Autodesk Fusion 360 part; units mm, degrees
(part 2 of 2)
equation "spigot_d = 8.5 mm" comment "ASSUMPTION: register FR-05: hole for the 8 mm locating spigot H-05"
equation "spigot_slot = 14 mm" comment "ASSUMPTION: register FR-05: slot length for the second spigot"
equation "spigot_edge = spigot_inset" comment "CALCULATION: the skeleton's spigot_inset: spigots 100 from each end of the edge (PM ruling 2026-10-31, R-J13)"
equation "bolt_edge = bolt_edge_inset" comment "CALCULATION: the skeleton's bolt_edge_inset: end bolts 220 in from the panel's ends, evenly spaced, every bolt 30 or more from any stile (PM ruling 2026-10-31, R-J14)"
equation "n_side_jnt = 3" comment "SOURCE: register J-WALL-02, J-FRONT-01: 3 bolts up each side panel"
equation "side_jnt_pitch = ( pnl_h - 2 * bolt_edge ) / ( n_side_jnt - 1 )" comment "CALCULATION: equal pitch of the 3 bolts up the corner and decor joints"
equation "pocket_w = 60 mm" comment "ASSUMPTION: register FR-10: fill left out 60 x 60 next to each bolt for the key"
equation "corner_z0 = panel_z0 + back_ph + seam_gap" comment "CALCULATION: bottom of the back panel row this side panel meets at the corner (B1/B2 or B3/B4, skeleton P04)"
equation "corner_bolt_pitch = ( back_ph - 2 * bolt_edge ) / ( n_side_jnt - 1 )" comment "CALCULATION: J-WALL-02 bolts run along the back panel's edge: 220, 559.31, 898.61 on its 1118.61 (joints register 2.9)"
equation "n_len_bolt = n_base_bolt" comment "CALCULATION: the skeleton's n_base_bolt (4): the same count on J-WALL-01 and the J-CEIL-01 side edges (register 2.9)"
equation "ceil_bolt_pitch = ( wall_depth - 2 * bolt_edge ) / ( n_len_bolt - 1 )" comment "CALCULATION: J-CEIL-01 side edge: 4 bolts along the ceiling's 1495 from Y -645 (its front edge), 220 rule, pitch 351.67 on P04; CEILING drills the same (PM ruling 2026-10-31 16:55; joints register 2.9)"
equation "len_bolt_pitch = ( pnl_len - 2 * bolt_edge ) / ( n_len_bolt - 1 )" comment "CALCULATION: even pitch of the bolts along the panel"
equation "felt_t = 9 mm" comment "SOURCE: plan VT03-PET 9 mm PET felt; HW-SEL A3; D-31 (the factory's felt)"
equation "tray_t = 0.5 mm" comment "CONFIRMED: D-37: galvanised steel tray 0.5 mm"
equation "tray_h = cass_t" comment "CONFIRMED: PM ruling 2026-10-31 (WALL group, option 1): the wall cassettes use the ceiling's tray, returns the full cassette depth (34) turned in as lips that hold the felt, no ribs; settles H09 for the walls"
equation "lip_w = 12 mm" comment "CONFIRMED: PM ruling 2026-10-31 (WALL group, option 1): 12 mm lips hold the felt edge"
equation "bend_r = tray_t" comment "ASSUMPTION: inside bend radius 1 x t for 0.5 mm DX51D (the sheet metal rule's bend radius is its Thickness); the factory's tooling sets it (guideline 9)"
equation "felt_c = 1 mm" comment "ASSUMPTION: felt edge clearance inside the returns, as the ceiling cassette"
equation "gap_h = tray_h - felt_t - 2 * tray_t" comment "CALCULATION: air gap between the tray base and the felt (24): the acoustic gap (D-17) and the cable path (D-26)"
equation "cass_len = wall_depth - stack_t + cass_t" comment "CALCULATION: = 1448: from the decor back plate to past the back cassette's face, closing the inside corner (D-57)"
equation "cass_h = pod_h - outer_t - lin_gap - ( panel_z0 + side_h + seam_gap )" comment "CALCULATION: lower: the panel height; upper: stops lin_gap under the roof frame so it floats (D-57)"
equation "clip_zone_h = 60 mm" comment "ASSUMPTION: height of each reserved clip zone (H03: no clip named)"
equation "clip_zone_dz = 100 mm" comment "ASSUMPTION: clip zone centre from the cassette's top and bottom edges (H03)"
equation "stopw_od = 20 mm" comment "SOURCE: joints register H-08: stop washer Ø10.5 x Ø20 x 1.5 (PROPOSED part)"
equation "stopw_id = 10.5 mm" comment "SOURCE: joints register H-08"
equation "stopw_t = 1.5 mm" comment "SOURCE: joints register H-08: rivnut head 0.76 + washer 1.5 = the 2.26 stop (R-J5)"
equation "rivnut_head_d = 12.96 mm" comment "SOURCE: Sherex CAH3-610-4.2 head Ø12.96 (joints register H-03, SHX)"
equation "rivnut_head_t = 0.76 mm" comment "SOURCE: Sherex CAH3-610-4.2 head 0.76 ±0.08 (H-03, SHX)"
equation "rivnut_body_d = 9.5 mm" comment "SOURCE: Sherex CAH3-610-4.2 body Ø9.50 max (H-03, SHX)"
equation "rivnut_len = 10.16 mm" comment "SOURCE: Sherex CAH3-610-4.2 installed length 10.16 max under the head (H-03, SHX); the bulge inside the tube is not modelled"
equation "m6_d = 6 mm" comment "CALCULATION: M6 threads shown at their 6 mm major diameter (no modelled thread)"
equation "spigot_pin_d = 8 mm" comment "SOURCE: joints register H-05: Ø8 stainless pin (PROPOSED, assumption sizes)"
equation "spigot_proud = 8 mm" comment "SOURCE: joints register H-05: stands 8 proud (read as: of the joint face)"
equation "spigot_thread_l = 10 mm" comment "ASSUMPTION: M6 thread into the spigot rivnut; H-05 gives no length; 10 stays inside the rivnut's 10.16"
equation "d165 = panel_z0 + side_h + seam_gap"
equation "d167 = ( ( pod_w / 2 - skin_t - bond_t ) ) - ( ( pod_w / 2 - outer_t ) )"
equation "d168 = ( pod_d / 2 - skin_t ) - ( pod_d / 2 - wall_depth + seam_gap )"
equation "d169 = abs(( pod_w / 2 - outer_t ))"
equation "d170 = abs(pod_d / 2 - wall_depth + seam_gap)"
equation "d171 = ( ( panel_z0 + side_h + seam_gap ) + tube_w ) - ( panel_z0 + side_h + seam_gap )"
equation "d173 = ( panel_z0 + side_h + seam_gap ) + tube_t"
equation "d175 = ( ( ( pod_w / 2 - skin_t - bond_t ) ) - tube_t ) - ( ( ( pod_w / 2 - outer_t ) ) + tube_t )"
equation "d176 = ( pod_d / 2 - skin_t ) - ( pod_d / 2 - wall_depth + seam_gap )"
equation "d177 = abs(( ( pod_w / 2 - outer_t ) ) + tube_t)"
equation "d178 = abs(pod_d / 2 - wall_depth + seam_gap)"
equation "d179 = ( ( ( panel_z0 + side_h + seam_gap ) + tube_w ) - tube_t ) - ( ( panel_z0 + side_h + seam_gap ) + tube_t )"
equation "d181 = ( pod_h ) - top_h"
equation "d183 = ( ( pod_w / 2 - skin_t - bond_t ) ) - ( ( pod_w / 2 - outer_t ) )"
equation "d184 = ( pod_d / 2 - skin_t ) - ( pod_d / 2 - wall_depth + seam_gap )"
equation "d185 = abs(( pod_w / 2 - outer_t ))"
equation "d186 = abs(pod_d / 2 - wall_depth + seam_gap)"
equation "d187 = ( pod_h ) - ( ( pod_h ) - top_h )"
equation "d189 = ( ( pod_h ) - top_h ) + tube_t"
equation "d191 = ( ( ( pod_w / 2 - skin_t - bond_t ) ) - tube_t ) - ( ( ( pod_w / 2 - outer_t ) ) + tube_t )"
equation "d192 = ( pod_d / 2 - skin_t ) - ( pod_d / 2 - wall_depth + seam_gap )"
equation "d193 = abs(( ( pod_w / 2 - outer_t ) ) + tube_t)"
equation "d194 = abs(pod_d / 2 - wall_depth + seam_gap)"
equation "d195 = ( ( pod_h ) - tube_t ) - ( ( ( pod_h ) - top_h ) + tube_t )"
equation "d197 = ( panel_z0 + side_h + seam_gap ) + tube_w"
equation "d199 = ( ( pod_w / 2 - skin_t - bond_t ) ) - ( ( pod_w / 2 - outer_t ) )"
equation "d200 = ( ( pod_d / 2 - wall_depth + seam_gap ) + tube_w ) - ( pod_d / 2 - wall_depth + seam_gap )"
equation "d201 = abs(( pod_w / 2 - outer_t ))"
equation "d202 = abs(pod_d / 2 - wall_depth + seam_gap)"
equation "d203 = ( ( pod_h ) - top_h ) - ( ( panel_z0 + side_h + seam_gap ) + tube_w )"
equation "d205 = ( panel_z0 + side_h + seam_gap ) + tube_w"
equation "d207 = ( ( ( pod_w / 2 - skin_t - bond_t ) ) - tube_t ) - ( ( ( pod_w / 2 - outer_t ) ) + tube_t )"
equation "d208 = ( ( ( pod_d / 2 - wall_depth + seam_gap ) + tube_w ) - tube_t ) - ( ( pod_d / 2 - wall_depth + seam_gap ) + tube_t )"
equation "d209 = abs(( ( pod_w / 2 - outer_t ) ) + tube_t)"
equation "d210 = abs(( pod_d / 2 - wall_depth + seam_gap ) + tube_t)"
equation "d211 = ( ( pod_h ) - top_h ) - ( ( panel_z0 + side_h + seam_gap ) + tube_w )"
equation "d213 = ( panel_z0 + side_h + seam_gap ) + tube_w"
equation "d215 = ( ( pod_w / 2 - skin_t - bond_t ) ) - ( ( pod_w / 2 - outer_t ) )"
equation "d216 = ( pod_d / 2 - skin_t ) - ( ( pod_d / 2 - skin_t ) - corner_w )"
equation "d217 = abs(( pod_w / 2 - outer_t ))"
equation "d218 = abs(( pod_d / 2 - skin_t ) - corner_w)"
equation "d219 = ( ( pod_h ) - top_h ) - ( ( panel_z0 + side_h + seam_gap ) + tube_w )"
equation "d221 = ( panel_z0 + side_h + seam_gap ) + tube_w"
equation "d223 = ( ( ( pod_w / 2 - skin_t - bond_t ) ) - tube_t ) - ( ( ( pod_w / 2 - outer_t ) ) + tube_t )"
equation "d224 = ( ( pod_d / 2 - skin_t ) - tube_t ) - ( ( ( pod_d / 2 - skin_t ) - corner_w ) + tube_t )"
equation "d225 = abs(( ( pod_w / 2 - outer_t ) ) + tube_t)"
equation "d226 = abs(( ( pod_d / 2 - skin_t ) - corner_w ) + tube_t)"
equation "d227 = ( ( pod_h ) - top_h ) - ( ( panel_z0 + side_h + seam_gap ) + tube_w )"
equation "d229 = ( panel_z0 + side_h + seam_gap ) + tube_w"
equation "d231 = ( ( pod_w / 2 - skin_t - bond_t ) ) - ( ( pod_w / 2 - outer_t ) )"
equation "d232 = ( ( pod_d / 2 - wall_depth + seam_gap ) + stile_pitch + tube_w ) - ( ( pod_d / 2 - wall_depth + seam_gap ) + stile_pitch )"
equation "d233 = abs(( pod_w / 2 - outer_t ))"
equation "d234 = abs(( pod_d / 2 - wall_depth + seam_gap ) + stile_pitch)"
equation "d235 = ( ( pod_h ) - top_h ) - ( ( panel_z0 + side_h + seam_gap ) + tube_w )"
equation "d237 = ( panel_z0 + side_h + seam_gap ) + tube_w"
equation "d239 = ( ( ( pod_w / 2 - skin_t - bond_t ) ) - stud_t ) - ( ( ( pod_w / 2 - outer_t ) ) + stud_t )"
equation "d240 = ( ( ( pod_d / 2 - wall_depth + seam_gap ) + stile_pitch + tube_w ) - stud_t ) - ( ( ( pod_d / 2 - wall_depth + seam_gap ) + stile_pitch ) + stud_t )"
equation "d241 = abs(( ( pod_w / 2 - outer_t ) ) + stud_t)"
equation "d242 = abs(( ( pod_d / 2 - wall_depth + seam_gap ) + stile_pitch ) + stud_t)"
equation "d243 = ( ( pod_h ) - top_h ) - ( ( panel_z0 + side_h + seam_gap ) + tube_w )"
equation "d245 = stile_n_mid"
equation "d247 = stile_pitch"
equation "d249 = ( panel_z0 + side_h + seam_gap ) + skin_setback"
equation "d251 = ( ( pod_w / 2 ) ) - ( ( pod_w / 2 - skin_t ) )"
equation "d252 = ( pod_d / 2 ) - ( pod_d / 2 - wall_depth + seam_gap )"
equation "d253 = abs(( pod_w / 2 - skin_t ))"
equation "d254 = abs(pod_d / 2 - wall_depth + seam_gap)"
equation "d255 = ( pod_h ) - ( ( panel_z0 + side_h + seam_gap ) + skin_setback )"
equation "d257 = ( panel_z0 + side_h + seam_gap ) + skin_setback"
equation "d259 = ( ( pod_w / 2 - skin_t ) ) - ( ( pod_w / 2 - skin_t - skin_ret ) )"
equation "d260 = ( pod_d / 2 ) - ( pod_d / 2 - skin_t )"
equation "d261 = abs(( pod_w / 2 - skin_t - skin_ret ))"
equation "d262 = abs(pod_d / 2 - skin_t)"
equation "d263 = ( pod_h ) - ( ( panel_z0 + side_h + seam_gap ) + skin_setback )"
equation "d265 = ( panel_z0 + side_h + seam_gap ) + tube_w"
equation "d267 = ( ( pod_w / 2 - skin_t - bond_t ) ) - ( ( pod_w / 2 - outer_t ) )"
equation "d268 = ( ( pod_d / 2 - wall_depth + seam_gap ) + stile_pitch ) - ( ( pod_d / 2 - wall_depth + seam_gap ) + tube_w )"
equation "d269 = abs(( pod_w / 2 - outer_t ))"
equation "d270 = abs(( pod_d / 2 - wall_depth + seam_gap ) + tube_w)"
equation "d271 = ( ( pod_h ) - top_h ) - ( ( panel_z0 + side_h + seam_gap ) + tube_w )"
equation "d273 = stile_n_mid"
equation "d275 = stile_pitch"
equation "d277 = ( panel_z0 + side_h + seam_gap ) + tube_w"
equation "d279 = ( ( pod_w / 2 - skin_t - bond_t ) ) - ( ( pod_w / 2 - outer_t ) )"
equation "d280 = ( ( pod_d / 2 - skin_t ) - corner_w ) - ( ( pod_d / 2 - wall_depth + seam_gap ) + stile_n_mid * stile_pitch + tube_w )"
equation "d281 = abs(( pod_w / 2 - outer_t ))"
equation "d282 = abs(( pod_d / 2 - wall_depth + seam_gap ) + stile_n_mid * stile_pitch + tube_w)"
equation "d283 = ( ( pod_h ) - top_h ) - ( ( panel_z0 + side_h + seam_gap ) + tube_w )"
equation "d285 = ( panel_z0 + side_h + seam_gap ) + tube_w"
equation "d287 = ( ( pod_w / 2 - skin_t - bond_t ) ) - ( ( pod_w / 2 - outer_t ) )"
equation "d288 = ( ( ( pod_d / 2 - wall_depth + seam_gap ) + bolt_edge + 0 * len_bolt_pitch ) + pocket_w / 2 ) - ( ( ( pod_d / 2 - wall_depth + seam_gap ) + bolt_edge + 0 * len_bolt_pitch ) - pocket_w / 2 )"
equation "d289 = abs(( pod_w / 2 - outer_t ))"
equation "d290 = abs(( ( pod_d / 2 - wall_depth + seam_gap ) + bolt_edge + 0 * len_bolt_pitch ) - pocket_w / 2)"
equation "d291 = ( ( ( panel_z0 + side_h + seam_gap ) + tube_w ) + pocket_w ) - ( ( panel_z0 + side_h + seam_gap ) + tube_w )"
equation "d293 = ( panel_z0 + side_h + seam_gap ) + tube_w"
equation "d295 = ( ( pod_w / 2 - skin_t - bond_t ) ) - ( ( pod_w / 2 - outer_t ) )"
equation "d296 = ( ( ( pod_d / 2 - wall_depth + seam_gap ) + bolt_edge + 1 * len_bolt_pitch ) + pocket_w / 2 ) - ( ( ( pod_d / 2 - wall_depth + seam_gap ) + bolt_edge + 1 * len_bolt_pitch ) - pocket_w / 2 )"
equation "d297 = abs(( pod_w / 2 - outer_t ))"
equation "d298 = abs(( ( pod_d / 2 - wall_depth + seam_gap ) + bolt_edge + 1 * len_bolt_pitch ) - pocket_w / 2)"
equation "d299 = ( ( ( panel_z0 + side_h + seam_gap ) + tube_w ) + pocket_w ) - ( ( panel_z0 + side_h + seam_gap ) + tube_w )"
equation "d301 = ( panel_z0 + side_h + seam_gap ) + tube_w"
equation "d303 = ( ( pod_w / 2 - skin_t - bond_t ) ) - ( ( pod_w / 2 - outer_t ) )"
equation "d304 = ( ( ( pod_d / 2 - wall_depth + seam_gap ) + bolt_edge + 2 * len_bolt_pitch ) + pocket_w / 2 ) - ( ( ( pod_d / 2 - wall_depth + seam_gap ) + bolt_edge + 2 * len_bolt_pitch ) - pocket_w / 2 )"
equation "d305 = abs(( pod_w / 2 - outer_t ))"
equation "d306 = abs(( ( pod_d / 2 - wall_depth + seam_gap ) + bolt_edge + 2 * len_bolt_pitch ) - pocket_w / 2)"
equation "d307 = ( ( ( panel_z0 + side_h + seam_gap ) + tube_w ) + pocket_w ) - ( ( panel_z0 + side_h + seam_gap ) + tube_w )"
equation "d309 = ( panel_z0 + side_h + seam_gap ) + tube_w"
equation "d311 = ( ( pod_w / 2 - skin_t - bond_t ) ) - ( ( pod_w / 2 - outer_t ) )"
equation "d312 = ( ( ( pod_d / 2 - wall_depth + seam_gap ) + bolt_edge + 3 * len_bolt_pitch ) + pocket_w / 2 ) - ( ( ( pod_d / 2 - wall_depth + seam_gap ) + bolt_edge + 3 * len_bolt_pitch ) - pocket_w / 2 )"
equation "d313 = abs(( pod_w / 2 - outer_t ))"
equation "d314 = abs(( ( pod_d / 2 - wall_depth + seam_gap ) + bolt_edge + 3 * len_bolt_pitch ) - pocket_w / 2)"
equation "d315 = ( ( ( panel_z0 + side_h + seam_gap ) + tube_w ) + pocket_w ) - ( ( panel_z0 + side_h + seam_gap ) + tube_w )"
equation "d317 = ( ( ( panel_z0 + side_h + seam_gap ) + bolt_edge ) + 0 * side_jnt_pitch ) - pocket_w / 2"
equation "d319 = ( ( pod_w / 2 - skin_t - bond_t ) ) - ( ( pod_w / 2 - outer_t ) )"
equation "d320 = ( ( pod_d / 2 - wall_depth + seam_gap ) + tube_w + pocket_w ) - ( ( pod_d / 2 - wall_depth + seam_gap ) + tube_w )"
equation "d321 = abs(( pod_w / 2 - outer_t ))"
equation "d322 = abs(( pod_d / 2 - wall_depth + seam_gap ) + tube_w)"
equation "d323 = ( ( ( ( panel_z0 + side_h + seam_gap ) + bolt_edge ) + 0 * side_jnt_pitch ) + pocket_w / 2 ) - ( ( ( ( panel_z0 + side_h + seam_gap ) + bolt_edge ) + 0 * side_jnt_pitch ) - pocket_w / 2 )"
equation "d325 = ( ( ( panel_z0 + side_h + seam_gap ) + bolt_edge ) + 1 * side_jnt_pitch ) - pocket_w / 2"
equation "d327 = ( ( pod_w / 2 - skin_t - bond_t ) ) - ( ( pod_w / 2 - outer_t ) )"
equation "d328 = ( ( pod_d / 2 - wall_depth + seam_gap ) + tube_w + pocket_w ) - ( ( pod_d / 2 - wall_depth + seam_gap ) + tube_w )"
equation "d329 = abs(( pod_w / 2 - outer_t ))"
equation "d330 = abs(( pod_d / 2 - wall_depth + seam_gap ) + tube_w)"
equation "d331 = ( ( ( ( panel_z0 + side_h + seam_gap ) + bolt_edge ) + 1 * side_jnt_pitch ) + pocket_w / 2 ) - ( ( ( ( panel_z0 + side_h + seam_gap ) + bolt_edge ) + 1 * side_jnt_pitch ) - pocket_w / 2 )"
equation "d333 = ( ( ( panel_z0 + side_h + seam_gap ) + bolt_edge ) + 2 * side_jnt_pitch ) - pocket_w / 2"
equation "d335 = ( ( pod_w / 2 - skin_t - bond_t ) ) - ( ( pod_w / 2 - outer_t ) )"
equation "d336 = ( ( pod_d / 2 - wall_depth + seam_gap ) + tube_w + pocket_w ) - ( ( pod_d / 2 - wall_depth + seam_gap ) + tube_w )"
equation "d337 = abs(( pod_w / 2 - outer_t ))"
equation "d338 = abs(( pod_d / 2 - wall_depth + seam_gap ) + tube_w)"
equation "d339 = ( ( ( ( panel_z0 + side_h + seam_gap ) + bolt_edge ) + 2 * side_jnt_pitch ) + pocket_w / 2 ) - ( ( ( ( panel_z0 + side_h + seam_gap ) + bolt_edge ) + 2 * side_jnt_pitch ) - pocket_w / 2 )"
equation "d341 = panel_z0 + side_h + seam_gap"
equation "d343 = abs(( pod_w / 2 - skin_t - bond_t - tube_d / 2 ))"
equation "d344 = abs(( pod_d / 2 - wall_depth + seam_gap ) + bolt_edge)"
equation "d345 = tube_t"
equation "d346 = bolt_d"
equation "d348 = ( panel_z0 + side_h + seam_gap ) + tube_w"
equation "d350 = abs(( pod_w / 2 - skin_t - bond_t - tube_d / 2 ))"
equation "d351 = abs(( pod_d / 2 - wall_depth + seam_gap ) + bolt_edge)"
equation "d352 = tube_t"
equation "d353 = access_d"
equation "d355 = n_len_bolt"
equation "d357 = len_bolt_pitch"
equation "d359 = panel_z0 + side_h + seam_gap"
equation "d361 = abs(( pod_w / 2 - skin_t - bond_t - tube_d / 2 ))"
equation "d362 = abs(( pod_d / 2 - wall_depth + seam_gap ) + spigot_edge)"
equation "d363 = tube_t"
equation "d364 = spigot_d"
equation "d366 = panel_z0 + side_h + seam_gap"
equation "d368 = ( ( ( pod_w / 2 - skin_t - bond_t - tube_d / 2 ) ) + ( spigot_slot - spigot_d ) / 2 ) - ( ( ( pod_w / 2 - skin_t - bond_t - tube_d / 2 ) ) - ( spigot_slot - spigot_d ) / 2 )"
equation "d369 = ( ( ( pod_d / 2 ) - spigot_edge ) + spigot_d / 2 ) - ( ( ( pod_d / 2 ) - spigot_edge ) - spigot_d / 2 )"
equation "d370 = abs(( ( pod_w / 2 - skin_t - bond_t - tube_d / 2 ) ) - ( spigot_slot - spigot_d ) / 2)"
equation "d371 = abs(( ( pod_d / 2 ) - spigot_edge ) - spigot_d / 2)"
equation "d372 = ( ( panel_z0 + side_h + seam_gap ) + tube_t ) - ( panel_z0 + side_h + seam_gap )"
equation "d374 = panel_z0 + side_h + seam_gap"
equation "d376 = abs(( ( pod_w / 2 - skin_t - bond_t - tube_d / 2 ) ) - ( spigot_slot - spigot_d ) / 2)"
equation "d377 = abs(( pod_d / 2 ) - spigot_edge)"
equation "d378 = tube_t"
equation "d379 = spigot_d"
equation "d381 = panel_z0 + side_h + seam_gap"
equation "d383 = abs(( ( pod_w / 2 - skin_t - bond_t - tube_d / 2 ) ) + ( spigot_slot - spigot_d ) / 2)"
equation "d384 = abs(( pod_d / 2 ) - spigot_edge)"
equation "d385 = tube_t"
equation "d386 = spigot_d"
equation "d388 = ( pod_w / 2 - outer_t )"
equation "d390 = abs(( pod_d / 2 - wall_depth ) + bolt_edge)"
equation "d391 = abs(pod_h - ceil_bolt_dz)"
equation "d392 = tube_t"
equation "d393 = rivnut_d"
equation "d395 = n_len_bolt"
equation "d397 = ceil_bolt_pitch"
equation "d399 = pod_d / 2 - wall_depth + seam_gap"
equation "d401 = abs(( pod_w / 2 - skin_t - bond_t - tube_d / 2 ))"
equation "d402 = abs(( panel_z0 + side_h + seam_gap ) + bolt_edge)"
equation "d403 = tube_t"
equation "d404 = bolt_d"
equation "d406 = ( pod_d / 2 - wall_depth + seam_gap ) + tube_w"
equation "d408 = abs(( pod_w / 2 - skin_t - bond_t - tube_d / 2 ))"
equation "d409 = abs(( panel_z0 + side_h + seam_gap ) + bolt_edge)"
equation "d410 = tube_t"
equation "d411 = access_d"
equation "d413 = n_side_jnt"
equation "d415 = side_jnt_pitch"
equation "d417 = ( pod_w / 2 - outer_t )"
equation "d419 = abs(bolt_line_y)"
equation "d420 = abs(corner_z0 + bolt_edge)"
equation "d421 = tube_t"
equation "d422 = rivnut_d"
equation "d424 = n_side_jnt"
equation "d426 = corner_bolt_pitch"
equation "d428 = ( pod_w / 2 - outer_t )"
equation "d430 = abs(( pod_d / 2 - wall_depth ) + bolt_edge)"
equation "d431 = abs(pod_h - ceil_bolt_dz)"
equation "d432 = stopw_od"
equation "d433 = stopw_id"
equation "d436 = -( stopw_t )"
equation "d438 = ( ( pod_w / 2 - outer_t ) ) - stopw_t"
equation "d440 = abs(( pod_d / 2 - wall_depth ) + bolt_edge)"
equation "d441 = abs(pod_h - ceil_bolt_dz)"
equation "d442 = rivnut_head_d"
equation "d443 = m6_d"
equation "d446 = -( rivnut_head_t )"
equation "d448 = ( ( pod_w / 2 - outer_t ) ) - stopw_t"
equation "d450 = abs(( pod_d / 2 - wall_depth ) + bolt_edge)"
equation "d451 = abs(pod_h - ceil_bolt_dz)"
equation "d452 = rivnut_body_d"
equation "d453 = m6_d"
equation "d454 = rivnut_len"
equation "d456 = n_len_bolt"
equation "d458 = ceil_bolt_pitch"
equation "d460 = n_len_bolt"
equation "d462 = ceil_bolt_pitch"
equation "d464 = ( pod_w / 2 - outer_t )"
equation "d466 = abs(bolt_line_y)"
equation "d467 = abs(corner_z0 + bolt_edge)"
equation "d468 = stopw_od"
equation "d469 = stopw_id"
equation "d472 = -( stopw_t )"
equation "d474 = ( ( pod_w / 2 - outer_t ) ) - stopw_t"
equation "d476 = abs(bolt_line_y)"
equation "d477 = abs(corner_z0 + bolt_edge)"
equation "d478 = rivnut_head_d"
equation "d479 = m6_d"
equation "d482 = -( rivnut_head_t )"
equation "d484 = ( ( pod_w / 2 - outer_t ) ) - stopw_t"
equation "d486 = abs(bolt_line_y)"
equation "d487 = abs(corner_z0 + bolt_edge)"
equation "d488 = rivnut_body_d"
equation "d489 = m6_d"
equation "d490 = rivnut_len"
equation "d492 = n_side_jnt"
equation "d494 = corner_bolt_pitch"
equation "d496 = n_side_jnt"
equation "d498 = corner_bolt_pitch"
named bodies: "RAIL - BOTTOM", "RAIL - TOP", "STILE - FRONT", "STILE - BACK", "STILE - MID 1", "STILE - MID 2", "STILE - MID 3", "SKIN - ACP 3 WITH BACK RETURN", "FILL - BAY 1", "FILL - BAY 2", "FILL - BAY 3", "FILL - BAY 4", "STOP WASHER - TOP MEMBER CEILING 1", "RIVNUT - TOP MEMBER CEILING 1", "STOP WASHER - TOP MEMBER CEILING 2", "STOP WASHER - TOP MEMBER CEILING 3", "STOP WASHER - TOP MEMBER CEILING 4", "RIVNUT - TOP MEMBER CEILING 2", "RIVNUT - TOP MEMBER CEILING 3", "RIVNUT - TOP MEMBER CEILING 4", "STOP WASHER - BACK STILE CORNER 1", "RIVNUT - BACK STILE CORNER 1", "STOP WASHER - BACK STILE CORNER 2", "STOP WASHER - BACK STILE CORNER 3", "RIVNUT - BACK STILE CORNER 2", "RIVNUT - BACK STILE CORNER 3"
